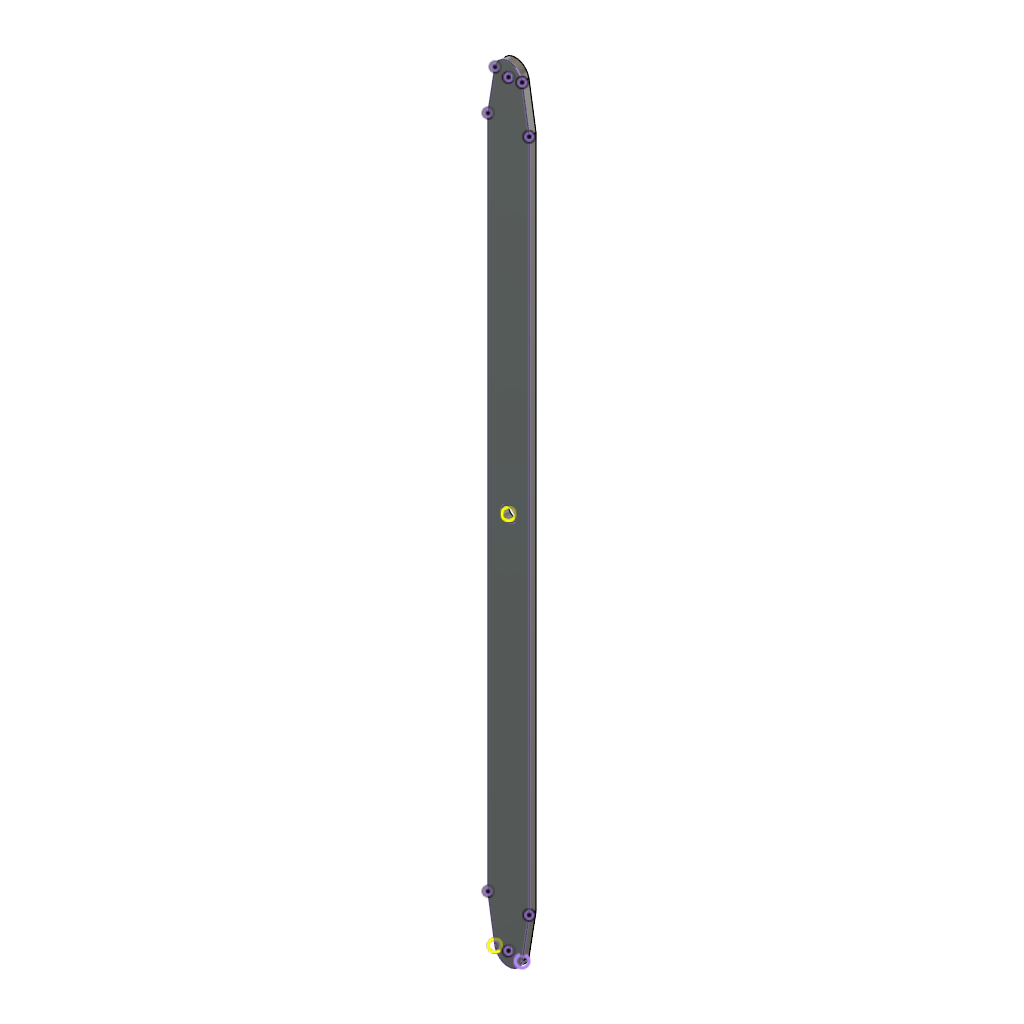
Swift Strut (Autodesk Fusion 360 design; units mm, degrees)
Autodesk Fusion 360 part; units mm, degrees
sketch "Geometry" plane through (0, 0, 0) normal (0, 0, 1) x (1, 0, 0)
  line L0 (0.4944, 0) -> (0.0008, -225.263)
  line L1 (10.0194, 180.975) -> (-9.0306, 180.975) construction
  line L2 (-9.0306, 180.975) -> (-9.0306, -180.975) construction
  line L3 (-9.0306, -180.975) -> (10.0194, -180.975) construction
  line L4 (10.0194, -180.975) -> (10.0194, 180.975) construction
  line L5 (10.0194, 180.975) -> (-9.0306, -180.975) construction
  line L6 (-9.0306, 180.975) -> (10.0194, -180.975) construction
  line L7 (-38.1, 0) -> (38.1, 0) construction
  line L8 (-9.0306, 155.575) -> (10.0194, 155.575) construction
  circle A0 centre (0.4944, 174.625) radius 2.032
  circle A1 centre (0.4944, 174.625) radius 6.35 construction
  line L9 (-9.0306, 155.575) -> (-5.7736, 175.6423)
  line L10 (10.0194, 155.575) -> (6.7623, 175.6423)
  arc A2 (6.7623, 175.6423) -> (-5.7736, 175.6423) centre (0.4944, 174.625) ccw
  line L11 (-9.0306, 155.575) -> (-9.0306, 0)
  line L12 (10.0194, 0) -> (10.0194, 155.575)
  line L13 (-9.0306, -155.575) -> (-9.0306, 0)
  line L14 (10.0194, 0) -> (10.0194, -155.575)
  line L15 (-9.0306, -155.575) -> (-5.7736, -175.6423)
  line L16 (10.0194, -155.575) -> (6.7623, -175.6423)
  arc A3 (-5.7736, -175.6423) -> (6.7623, -175.6423) centre (0.4944, -174.625) ccw
  circle A4 centre (0.4944, -174.625) radius 2.032
  line L17 (0.4944, 180.975) -> (0.4944, 174.625) construction
  circle A5 centre (0.4944, 0) radius 3.175
  point P0 (0.4944, 0)
  dimension "d33" = 19.05
  dimension "d35" = 25.4
  dimension "d36" = 4.064
  dimension "d37" = 6.35
  dimension "d38" = 6.35
  dimension "d39" = 180.975
  dimension "d41" = 361.95
  dimension "d42" = 6.35
  constraint horizontal L1
  constraint perpendicular L1 L2
  constraint parallel L1 L3
  constraint parallel L2 L4
  constraint coincident L5 P0
  constraint coincident L6 P0
  constraint coincident P0 L0.start
  constraint perpendicular L4 L7
  constraint coincident L2 L8.start
  constraint coincident L4 L8.end
  constraint perpendicular L4 L8
  constraint concentric A0 A1
  constraint tangent L1 A1
  constraint coincident A1 L9.end
  constraint tangent A1 L9
  constraint coincident A1 L10.end
  constraint tangent A1 L10
  constraint tangent L1 A2
  constraint midpoint L2 L11.end
  constraint midpoint L4 L12.start
  constraint symmetric L7 L8.start L13.start
  constraint symmetric L7 L8.end L14.end
  constraint symmetric L7 A0 A4
  constraint symmetric L7 L9.end L15.end
  constraint symmetric L7 L10.end L16.end
  constraint symmetric L7 A2 A3
  constraint symmetric L7 L11.end L13.end
  constraint symmetric L7 L12.start L14.start
  constraint tangent L3 A3
  constraint midpoint A2 L17.start
  constraint coincident A0.centre A1.centre
  constraint vertical L17
  constraint coincident L7 origin
  measures "d33" distance of L2.end L3.end
  measures "d35" distance of L1 L8
  measures "d36" diameter of A0
  measures "d37" distance of L1 A0.centre
  measures "d38" radius of A2
  measures "d39" distance of L1 L7
  measures "d41" distance of L1 L3
  measures "d42" diameter of A5
extrude "Extrude1" add sketch "Geometry" along normal blind 3.175
sketch "For Export" plane through (0, 0, 3.175) normal (0, 0, 1) x (1, 0, 0)
  line L0 (-9.0306, -155.575) -> (-5.7736, -175.6423)
  line L1 (10.0194, 155.575) -> (6.7623, 175.6423)
  line L2 (6.7623, -175.6423) -> (10.0194, -155.575)
  arc A0 (-5.7736, -175.6423) -> (6.7623, -175.6423) centre (0.4944, -174.625) ccw
  line L3 (-5.7736, 175.6423) -> (-9.0306, 155.575)
  line L4 (-9.0306, 155.575) -> (-9.0306, -155.575)
  circle A1 centre (0.4944, 0) radius 3.175
  circle A2 centre (0.4944, -174.625) radius 2.032
  line L5 (10.0194, -155.575) -> (10.0194, 155.575)
  arc A3 (6.7623, 175.6423) -> (-5.7736, 175.6423) centre (0.4944, 174.625) ccw
  circle A4 centre (0.4944, 174.625) radius 2.032
